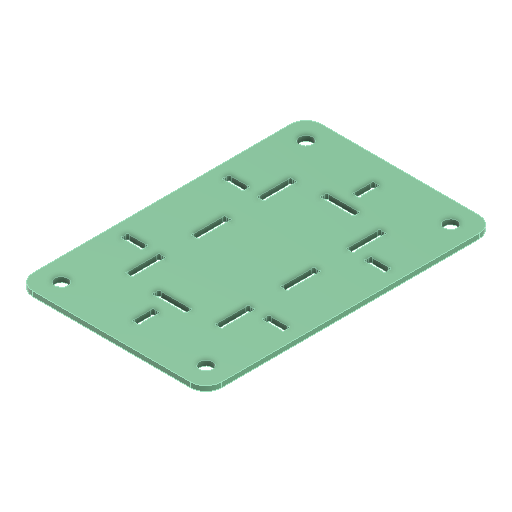
# Autodesk Inventor part: CUT_FR4_Waveguide_Back_Plate
Saved by Autodesk Inventor 2026.1 (Build 301233000, 233)
## iProperties
Created: 2025-11-04
Part Number: CUT_FR4_Waveguide_Back_Plate
Material: Generic
Document SubType Name: Modeling
Designer: User
Density: 1 g/cm^3
Appearance: Smooth - Dark Sea Green
Author: User
Autodesk Inventor part; units mm, degrees
ref_plane "YZ Plane" through (0, 0, 0) normal (1, 0, 0) x (0, 1, 0)
ref_plane "XZ Plane" through (0, 0, 0) normal (0, 1, 0) x (-1, 0, 0)
ref_plane "XY Plane" through (0, 0, 0) normal (0, 0, 1) x (1, 0, 0)
sketch "Sketch1" plane through (0, 0, 0) normal (0, 1, 0) x (-1, 0, 0)
  line L0 (14.0049, 35.6184) -> (-15.9951, 35.6184)
  line L1 (-15.9951, 35.6184) -> (-15.9951, -26.1816)
  line L2 (-15.9951, -26.1816) -> (14.0049, -26.1816)
  line L3 (14.0049, -26.1816) -> (14.0049, 35.6184)
  line L4 (29.0049, 50.6184) -> (-30.9951, 50.6184)
  line L5 (-30.9951, 50.6184) -> (-30.9951, -41.1816)
  line L6 (-30.9951, -41.1816) -> (29.0049, -41.1816)
  line L7 (29.0049, -41.1816) -> (29.0049, 50.6184)
  point P0 (0, 0)
  dimension "d0" = 30
  dimension "d1" = 61.8
  dimension "d4" = 15
  constraints: 16 end point, 4 parallel, 2 perpendicular, 1 horizontal, 3 other
  measures "d0" distance of L2.end L1.end
  measures "d1" distance of L1.end L0.end
  measures "d4" distance between parallel lines of L3 L7
extrude "Extrusion1" add sketch "Sketch1" along normal blind 1.6 contours L3 L2 L1 L0 | L7 L6 L5 L4
sketch "Sketch2" plane through (0, 1.6, 0) normal (0, 1, 0) x (1, 0, 0)
  line L0 (14.3951, 21.1816) -> (14.3951, 11.1816) construction
  line L1 (14.3951, 11.1816) -> (15.9951, 11.1816) construction
  line L2 (15.9951, 11.1816) -> (15.9951, 21.1816) construction
  line L3 (15.9951, 21.1816) -> (14.3951, 21.1816) construction
  line L4 (14.1451, 21.4316) -> (14.1451, 10.9316)
  line L5 (14.1451, 10.9316) -> (16.2451, 10.9316)
  line L6 (16.2451, 10.9316) -> (16.2451, 21.4316)
  line L7 (16.2451, 21.4316) -> (14.1451, 21.4316)
  line L8 (14.3951, 0.2816) -> (14.3951, -9.7184) construction
  line L9 (14.3951, -9.7184) -> (15.9951, -9.7184) construction
  line L10 (15.9951, -9.7184) -> (15.9951, 0.2816) construction
  line L11 (15.9951, 0.2816) -> (14.3951, 0.2816) construction
  line L12 (14.1451, 0.5316) -> (14.1451, -9.9684)
  line L13 (14.1451, -9.9684) -> (16.2451, -9.9684)
  line L14 (16.2451, -9.9684) -> (16.2451, 0.5316)
  line L15 (16.2451, 0.5316) -> (14.1451, 0.5316)
  line L16 (14.3951, -20.6184) -> (14.3951, -30.6184) construction
  line L17 (14.3951, -30.6184) -> (15.9951, -30.6184) construction
  line L18 (15.9951, -30.6184) -> (15.9951, -20.6184) construction
  line L19 (15.9951, -20.6184) -> (14.3951, -20.6184) construction
  line L20 (14.1451, -20.3684) -> (14.1451, -30.8684)
  line L21 (14.1451, -30.8684) -> (16.2451, -30.8684)
  line L22 (16.2451, -30.8684) -> (16.2451, -20.3684)
  line L23 (16.2451, -20.3684) -> (14.1451, -20.3684)
  dimension "d5" = 0.25
  dimension "d6" = 0.25
  dimension "d7" = 0.25
  constraints: 24 end point, 9 other
  measures "d5" distance between parallel lines of L4 L0
  measures "d6" distance between parallel lines of L12 L8
  measures "d7" distance between parallel lines of L20 L16
extrude "Extrusion2" cut sketch "Sketch2" against normal up to next
sketch "Sketch3" plane through (0, 1.6, 0) normal (0, 1, 0) x (1, 0, 0)
  circle A0 centre (15.8916, 0.178) radius 0.5
  circle A1 centre (15.8916, -9.6149) radius 0.5
  circle A2 centre (14.4987, -9.6149) radius 0.5
  circle A3 centre (14.4987, 0.178) radius 0.5
  circle A4 centre (15.8916, 21.078) radius 0.5
  circle A5 centre (15.8916, 11.2851) radius 0.5
  circle A6 centre (14.4987, 11.2851) radius 0.5
  circle A7 centre (14.4987, 21.078) radius 0.5
  circle A8 centre (15.8916, -20.722) radius 0.5
  circle A9 centre (15.8916, -30.5149) radius 0.5
  circle A10 centre (14.4987, -30.5149) radius 0.5
  circle A11 centre (14.4987, -20.722) radius 0.5
  point P0 (14.1451, 0.5316)
  point P1 (16.2451, -9.9684)
  point P2 (16.2451, 0.5316)
  point P3 (14.1451, -9.9684)
  point P4 (14.1451, 21.4316)
  point P5 (16.2451, 10.9316)
  point P6 (16.2451, 21.4316)
  point P7 (14.1451, 10.9316)
  point P8 (14.1451, -20.3684)
  point P9 (16.2451, -30.8684)
  point P10 (16.2451, -20.3684)
  point P11 (14.1451, -30.8684)
  dimension "d10" = 45
  dimension "d11" = 0.5
  dimension "d12" = 1
  dimension "d13" = 45
  dimension "d14" = 0.5
  dimension "d15" = 1
  dimension "d16" = 45
  dimension "d17" = 0.5
  dimension "d18" = 1
  dimension "d19" = 45
  dimension "d20" = 0.5
  dimension "d21" = 1
  dimension "d22" = 45
  dimension "d23" = 0.5
  dimension "d24" = 1
  dimension "d25" = 45
  dimension "d26" = 0.5
  dimension "d27" = 1
  dimension "d28" = 45
  dimension "d29" = 0.5
  dimension "d30" = 1
  dimension "d31" = 45
  dimension "d32" = 0.5
  dimension "d33" = 1
  dimension "d34" = 45
  dimension "d35" = 0.5
  dimension "d36" = 1
  dimension "d37" = 45
  dimension "d38" = 0.5
  dimension "d39" = 1
  dimension "d40" = 45
  dimension "d41" = 0.5
  dimension "d42" = 1
  dimension "d43" = 45
  dimension "d44" = 0.5
  dimension "d45" = 1
  constraints: 12 centre point
  measures "d11" distance of A0.centre point (16.245, 0.532)
  measures "d12" diameter of A0
  measures "d14" distance of A1.centre point (16.245, -9.968)
  measures "d15" diameter of A1
  measures "d17" distance of A2.centre point (14.145, -9.968)
  measures "d18" diameter of A2
  measures "d20" distance of A3.centre point (14.145, 0.532)
  measures "d21" diameter of A3
  measures "d23" distance of A4.centre point (16.245, 21.432)
  measures "d24" diameter of A4
  measures "d26" distance of A5.centre point (16.245, 10.932)
  measures "d27" diameter of A5
  measures "d29" distance of A6.centre point (14.145, 10.932)
  measures "d30" diameter of A6
  measures "d32" distance of A7.centre point (14.145, 21.432)
  measures "d33" diameter of A7
  measures "d35" distance of A8.centre point (16.245, -20.368)
  measures "d36" diameter of A8
  measures "d38" distance of A9.centre point (16.245, -30.868)
  measures "d39" diameter of A9
  measures "d41" distance of A10.centre point (14.145, -30.868)
  measures "d42" diameter of A10
  measures "d44" distance of A11.centre point (14.145, -20.368)
  measures "d45" diameter of A11
extrude "Extrusion3" cut sketch "Sketch3" against normal up to surface (1.6 mm away)
sketch "Sketch4" plane through (0, 1.6, 0) normal (0, 1, 0) x (1, 0, 0)
  line L0 (-12.4049, -30.6184) -> (-12.4049, -20.6184) construction
  line L1 (-12.4049, -20.6184) -> (-14.0049, -20.6184) construction
  line L2 (-14.0049, -20.6184) -> (-14.0049, -30.6184) construction
  line L3 (-14.0049, -30.6184) -> (-12.4049, -30.6184) construction
  line L4 (-12.1549, -30.8684) -> (-12.1549, -20.3684)
  line L5 (-12.1549, -20.3684) -> (-14.2549, -20.3684)
  line L6 (-14.2549, -20.3684) -> (-14.2549, -30.8684)
  line L7 (-14.2549, -30.8684) -> (-12.1549, -30.8684)
  line L8 (-12.4049, -9.7184) -> (-12.4049, 0.2816) construction
  line L9 (-12.4049, 0.2816) -> (-14.0049, 0.2816) construction
  line L10 (-14.0049, 0.2816) -> (-14.0049, -9.7184) construction
  line L11 (-14.0049, -9.7184) -> (-12.4049, -9.7184) construction
  line L12 (-12.1549, -9.9684) -> (-12.1549, 0.5316)
  line L13 (-12.1549, 0.5316) -> (-14.2549, 0.5316)
  line L14 (-14.2549, 0.5316) -> (-14.2549, -9.9684)
  line L15 (-14.2549, -9.9684) -> (-12.1549, -9.9684)
  line L16 (-12.4049, 11.1816) -> (-12.4049, 21.1816) construction
  line L17 (-12.4049, 21.1816) -> (-14.0049, 21.1816) construction
  line L18 (-14.0049, 21.1816) -> (-14.0049, 11.1816) construction
  line L19 (-14.0049, 11.1816) -> (-12.4049, 11.1816) construction
  line L20 (-12.1549, 10.9316) -> (-12.1549, 21.4316)
  line L21 (-12.1549, 21.4316) -> (-14.2549, 21.4316)
  line L22 (-14.2549, 21.4316) -> (-14.2549, 10.9316)
  line L23 (-14.2549, 10.9316) -> (-12.1549, 10.9316)
  dimension "d48" = 0.25
  dimension "d49" = 0.25
  dimension "d50" = 0.25
  constraints: 24 end point, 9 other
  measures "d48" distance between parallel lines of L4 L0
  measures "d49" distance between parallel lines of L12 L8
  measures "d50" distance between parallel lines of L20 L16
extrude "Extrusion4" cut sketch "Sketch4" against normal up to next
sketch "Sketch5" plane through (0, 1.6, 0) normal (0, 1, 0) x (1, 0, 0)
  circle A0 centre (-13.9013, -9.6149) radius 0.5
  circle A1 centre (-13.9013, 0.178) radius 0.5
  circle A2 centre (-12.5084, 0.178) radius 0.5
  circle A3 centre (-12.5084, -9.6149) radius 0.5
  circle A4 centre (-13.9013, -30.5149) radius 0.5
  circle A5 centre (-13.9013, -20.722) radius 0.5
  circle A6 centre (-12.5084, -20.722) radius 0.5
  circle A7 centre (-12.5084, -30.5149) radius 0.5
  circle A8 centre (-13.9013, 11.2851) radius 0.5
  circle A9 centre (-13.9013, 21.078) radius 0.5
  circle A10 centre (-12.5084, 21.078) radius 0.5
  circle A11 centre (-12.5084, 11.2851) radius 0.5
  point P0 (-12.1549, -9.9684)
  point P1 (-14.2549, 0.5316)
  point P2 (-14.2549, -9.9684)
  point P3 (-12.1549, 0.5316)
  point P4 (-12.1549, -30.8684)
  point P5 (-14.2549, -20.3684)
  point P6 (-14.2549, -30.8684)
  point P7 (-12.1549, -20.3684)
  point P8 (-12.1549, 10.9316)
  point P9 (-14.2549, 21.4316)
  point P10 (-14.2549, 10.9316)
  point P11 (-12.1549, 21.4316)
  dimension "d53" = 45
  dimension "d54" = 0.5
  dimension "d55" = 1
  dimension "d56" = 45
  dimension "d57" = 0.5
  dimension "d58" = 1
  dimension "d59" = 45
  dimension "d60" = 0.5
  dimension "d61" = 1
  dimension "d62" = 45
  dimension "d63" = 0.5
  dimension "d64" = 1
  dimension "d65" = 45
  dimension "d66" = 0.5
  dimension "d67" = 1
  dimension "d68" = 45
  dimension "d69" = 0.5
  dimension "d70" = 1
  dimension "d71" = 45
  dimension "d72" = 0.5
  dimension "d73" = 1
  dimension "d74" = 45
  dimension "d75" = 0.5
  dimension "d76" = 1
  dimension "d77" = 45
  dimension "d78" = 0.5
  dimension "d79" = 1
  dimension "d80" = 45
  dimension "d81" = 0.5
  dimension "d82" = 1
  dimension "d83" = 45
  dimension "d84" = 0.5
  dimension "d85" = 1
  dimension "d86" = 45
  dimension "d87" = 0.5
  dimension "d88" = 1
  constraints: 12 centre point
  measures "d54" distance of A0.centre point (-14.255, -9.968)
  measures "d55" diameter of A0
  measures "d57" distance of A1.centre point (-14.255, 0.532)
  measures "d58" diameter of A1
  measures "d60" distance of A2.centre point (-12.155, 0.532)
  measures "d61" diameter of A2
  measures "d63" distance of A3.centre point (-12.155, -9.968)
  measures "d64" diameter of A3
  measures "d66" distance of A4.centre point (-14.255, -30.868)
  measures "d67" diameter of A4
  measures "d69" distance of A5.centre point (-14.255, -20.368)
  measures "d70" diameter of A5
  measures "d72" distance of A6.centre point (-12.155, -20.368)
  measures "d73" diameter of A6
  measures "d75" distance of A7.centre point (-12.155, -30.868)
  measures "d76" diameter of A7
  measures "d78" distance of A8.centre point (-14.255, 10.932)
  measures "d79" diameter of A8
  measures "d81" distance of A9.centre point (-14.255, 21.432)
  measures "d82" diameter of A9
  measures "d84" distance of A10.centre point (-12.155, 21.432)
  measures "d85" diameter of A10
  measures "d87" distance of A11.centre point (-12.155, 10.932)
  measures "d88" diameter of A11
extrude "Extrusion5" cut sketch "Sketch5" against normal up to surface (1.6 mm away)
sketch "Sketch6" plane through (0, 1.6, 0) normal (0, 1, 0) x (1, 0, 0)
  line L0 (-4.0049, 21.1816) -> (5.9951, 21.1816) construction
  line L1 (5.9951, 21.1816) -> (5.9951, 22.7816) construction
  line L2 (5.9951, 22.7816) -> (-4.0049, 22.7816) construction
  line L3 (-4.0049, 22.7816) -> (-4.0049, 21.1816) construction
  line L4 (-4.2549, 20.9316) -> (6.2451, 20.9316)
  line L5 (6.2451, 20.9316) -> (6.2451, 23.0316)
  line L6 (6.2451, 23.0316) -> (-4.2549, 23.0316)
  line L7 (-4.2549, 23.0316) -> (-4.2549, 20.9316)
  dimension "d91" = 0.25
  constraints: 8 end point, 3 other
  measures "d91" distance between parallel lines of L4 L0
extrude "Extrusion6" cut sketch "Sketch6" against normal up to next
sketch "Sketch7" plane through (0, 1.6, 0) normal (0, 1, 0) x (1, 0, 0)
  circle A0 centre (-3.9013, 22.678) radius 0.5
  circle A1 centre (5.8916, 22.678) radius 0.5
  circle A2 centre (5.8916, 21.2851) radius 0.5
  circle A3 centre (-3.9013, 21.2851) radius 0.5
  point P0 (-4.2549, 20.9316)
  point P1 (6.2451, 23.0316)
  point P2 (-4.2549, 23.0316)
  point P3 (6.2451, 20.9316)
  dimension "d94" = 45
  dimension "d95" = 0.5
  dimension "d96" = 1
  dimension "d97" = 45
  dimension "d98" = 0.5
  dimension "d99" = 1
  dimension "d100" = 45
  dimension "d101" = 0.5
  dimension "d102" = 1
  dimension "d103" = 45
  dimension "d104" = 0.5
  dimension "d105" = 1
  constraints: 4 centre point
  measures "d95" distance of A0.centre point (-4.255, 23.032)
  measures "d96" diameter of A0
  measures "d98" distance of A1.centre point (6.245, 23.032)
  measures "d99" diameter of A1
  measures "d101" distance of A2.centre point (6.245, 20.932)
  measures "d102" diameter of A2
  measures "d104" distance of A3.centre point (-4.255, 20.932)
  measures "d105" diameter of A3
extrude "Extrusion7" cut sketch "Sketch7" against normal up to surface (1.6 mm away)
sketch "Sketch8" plane through (0, 1.6, 0) normal (0, 1, 0) x (1, 0, 0)
  line L0 (5.9951, -30.6184) -> (-4.0049, -30.6184) construction
  line L1 (-4.0049, -30.6184) -> (-4.0049, -32.2184) construction
  line L2 (-4.0049, -32.2184) -> (5.9951, -32.2184) construction
  line L3 (5.9951, -32.2184) -> (5.9951, -30.6184) construction
  line L4 (6.2451, -30.3684) -> (-4.2549, -30.3684)
  line L5 (-4.2549, -30.3684) -> (-4.2549, -32.4684)
  line L6 (-4.2549, -32.4684) -> (6.2451, -32.4684)
  line L7 (6.2451, -32.4684) -> (6.2451, -30.3684)
  dimension "d108" = 0.25
  constraints: 8 end point, 3 other
  measures "d108" distance between parallel lines of L4 L0
extrude "Extrusion8" cut sketch "Sketch8" against normal up to next
sketch "Sketch9" plane through (0, 1.6, 0) normal (0, 1, 0) x (1, 0, 0)
  circle A0 centre (5.8916, -32.1149) radius 0.5
  circle A1 centre (-3.9013, -32.1149) radius 0.5
  circle A2 centre (-3.9013, -30.722) radius 0.5
  circle A3 centre (5.8916, -30.722) radius 0.5
  point P0 (6.2451, -30.3684)
  point P1 (-4.2549, -32.4684)
  point P2 (6.2451, -32.4684)
  point P3 (-4.2549, -30.3684)
  dimension "d111" = 45
  dimension "d112" = 0.5
  dimension "d113" = 1
  dimension "d114" = 45
  dimension "d115" = 0.5
  dimension "d116" = 1
  dimension "d117" = 45
  dimension "d118" = 0.5
  dimension "d119" = 1
  dimension "d120" = 45
  dimension "d121" = 0.5
  dimension "d122" = 1
  constraints: 4 centre point
  measures "d112" distance of A0.centre point (6.245, -32.468)
  measures "d113" diameter of A0
  measures "d115" distance of A1.centre point (-4.255, -32.468)
  measures "d116" diameter of A1
  measures "d118" distance of A2.centre point (-4.255, -30.368)
  measures "d119" diameter of A2
  measures "d121" distance of A3.centre point (6.245, -30.368)
  measures "d122" diameter of A3
extrude "Extrusion9" cut sketch "Sketch9" against normal up to surface (1.6 mm away)
fillet "Fillet1" radius 5 4 edges at (30.9951, 0.8, 50.6184) (-29.0049, 0.8, 50.6184) (30.9951, 0.8, -41.1816) (-29.0049, 0.8, -41.1816)
sketch "Sketch10" plane through (0, 1.6, 0) normal (0, 1, 0) x (1, 0, 0)
  arc A0 (-24.0049, 41.1816) -> (-29.0049, 36.1816) centre (-24.0049, 36.1816) ccw projected
  line L0 (-29.0049, 36.1816) -> (-29.0049, -45.6184) projected
  arc A1 (-29.0049, -45.6184) -> (-24.0049, -50.6184) centre (-24.0049, -45.6184) ccw projected
  line L1 (-24.0049, -50.6184) -> (25.9951, -50.6184) projected
  arc A2 (25.9951, -50.6184) -> (30.9951, -45.6184) centre (25.9951, -45.6184) ccw projected
  line L2 (30.9951, -45.6184) -> (30.9951, 36.1816) projected
  arc A3 (30.9951, 36.1816) -> (25.9951, 41.1816) centre (25.9951, 36.1816) ccw projected
  line L3 (25.9951, 41.1816) -> (-24.0049, 41.1816) projected
  arc A4 (-3.5478, -30.3684) -> (-4.2549, -31.0756) centre (-3.9013, -30.722) ccw projected
  line L4 (-3.5478, -30.3684) -> (5.538, -30.3684) projected
  arc A5 (6.2451, -31.0756) -> (5.538, -30.3684) centre (5.8916, -30.722) ccw projected
  line L5 (6.2451, -31.0756) -> (6.2451, -31.7613) projected
  arc A6 (5.538, -32.4684) -> (6.2451, -31.7613) centre (5.8916, -32.1149) ccw projected
  line L6 (5.538, -32.4684) -> (-3.5478, -32.4684) projected
  arc A7 (-4.2549, -31.7613) -> (-3.5478, -32.4684) centre (-3.9013, -32.1149) ccw projected
  line L7 (-4.2549, -31.7613) -> (-4.2549, -31.0756) projected
  arc A8 (5.538, 20.9316) -> (6.2451, 21.6387) centre (5.8916, 21.2851) ccw projected
  line L8 (5.538, 20.9316) -> (-3.5478, 20.9316) projected
  arc A9 (-4.2549, 21.6387) -> (-3.5478, 20.9316) centre (-3.9013, 21.2851) ccw projected
  line L9 (-4.2549, 21.6387) -> (-4.2549, 22.3244) projected
  arc A10 (-3.5478, 23.0316) -> (-4.2549, 22.3244) centre (-3.9013, 22.678) ccw projected
  line L10 (-3.5478, 23.0316) -> (5.538, 23.0316) projected
  arc A11 (6.2451, 22.3244) -> (5.538, 23.0316) centre (5.8916, 22.678) ccw projected
  line L11 (6.2451, 22.3244) -> (6.2451, 21.6387) projected
  arc A12 (-12.1549, 20.7244) -> (-12.862, 21.4316) centre (-12.5084, 21.078) ccw projected
  line L12 (-12.1549, 20.7244) -> (-12.1549, 11.6387) projected
  arc A13 (-12.862, 10.9316) -> (-12.1549, 11.6387) centre (-12.5084, 11.2851) ccw projected
  line L13 (-12.862, 10.9316) -> (-13.5478, 10.9316) projected
  arc A14 (-14.2549, 11.6387) -> (-13.5478, 10.9316) centre (-13.9013, 11.2851) ccw projected
  line L14 (-14.2549, 11.6387) -> (-14.2549, 20.7244) projected
  arc A15 (-13.5478, 21.4316) -> (-14.2549, 20.7244) centre (-13.9013, 21.078) ccw projected
  line L15 (-13.5478, 21.4316) -> (-12.862, 21.4316) projected
  arc A16 (-12.862, -30.8684) -> (-12.1549, -30.1613) centre (-12.5084, -30.5149) ccw projected
  line L16 (-12.862, -30.8684) -> (-13.5478, -30.8684) projected
  arc A17 (-14.2549, -30.1613) -> (-13.5478, -30.8684) centre (-13.9013, -30.5149) ccw projected
  line L17 (-14.2549, -30.1613) -> (-14.2549, -21.0756) projected
  arc A18 (-13.5478, -20.3684) -> (-14.2549, -21.0756) centre (-13.9013, -20.722) ccw projected
  line L18 (-13.5478, -20.3684) -> (-12.862, -20.3684) projected
  arc A19 (-12.1549, -21.0756) -> (-12.862, -20.3684) centre (-12.5084, -20.722) ccw projected
  line L19 (-12.1549, -21.0756) -> (-12.1549, -30.1613) projected
  arc A20 (-12.862, -9.9684) -> (-12.1549, -9.2613) centre (-12.5084, -9.6149) ccw projected
  line L20 (-12.862, -9.9684) -> (-13.5478, -9.9684) projected
  arc A21 (-14.2549, -9.2613) -> (-13.5478, -9.9684) centre (-13.9013, -9.6149) ccw projected
  line L21 (-14.2549, -9.2613) -> (-14.2549, -0.1756) projected
  arc A22 (-13.5478, 0.5316) -> (-14.2549, -0.1756) centre (-13.9013, 0.178) ccw projected
  line L22 (-13.5478, 0.5316) -> (-12.862, 0.5316) projected
  arc A23 (-12.1549, -0.1756) -> (-12.862, 0.5316) centre (-12.5084, 0.178) ccw projected
  line L23 (-12.1549, -0.1756) -> (-12.1549, -9.2613) projected
  arc A24 (14.1451, -30.1613) -> (14.8522, -30.8684) centre (14.4987, -30.5149) ccw projected
  line L24 (14.1451, -30.1613) -> (14.1451, -21.0756) projected
  arc A25 (14.8522, -20.3684) -> (14.1451, -21.0756) centre (14.4987, -20.722) ccw projected
  line L25 (14.8522, -20.3684) -> (15.538, -20.3684) projected
  arc A26 (16.2451, -21.0756) -> (15.538, -20.3684) centre (15.8916, -20.722) ccw projected
  line L26 (16.2451, -21.0756) -> (16.2451, -30.1613) projected
  arc A27 (15.538, -30.8684) -> (16.2451, -30.1613) centre (15.8916, -30.5149) ccw projected
  line L27 (15.538, -30.8684) -> (14.8522, -30.8684) projected
  arc A28 (14.8522, 21.4316) -> (14.1451, 20.7244) centre (14.4987, 21.078) ccw projected
  line L28 (14.8522, 21.4316) -> (15.538, 21.4316) projected
  arc A29 (16.2451, 20.7244) -> (15.538, 21.4316) centre (15.8916, 21.078) ccw projected
  line L29 (16.2451, 20.7244) -> (16.2451, 11.6387) projected
  arc A30 (15.538, 10.9316) -> (16.2451, 11.6387) centre (15.8916, 11.2851) ccw projected
  line L30 (15.538, 10.9316) -> (14.8522, 10.9316) projected
  arc A31 (14.1451, 11.6387) -> (14.8522, 10.9316) centre (14.4987, 11.2851) ccw projected
  line L31 (14.1451, 11.6387) -> (14.1451, 20.7244) projected
  arc A32 (14.8522, 0.5316) -> (14.1451, -0.1756) centre (14.4987, 0.178) ccw projected
  line L32 (14.8522, 0.5316) -> (15.538, 0.5316) projected
  arc A33 (16.2451, -0.1756) -> (15.538, 0.5316) centre (15.8916, 0.178) ccw projected
  line L33 (16.2451, -0.1756) -> (16.2451, -9.2613) projected
  arc A34 (15.538, -9.9684) -> (16.2451, -9.2613) centre (15.8916, -9.6149) ccw projected
  line L34 (15.538, -9.9684) -> (14.8522, -9.9684) projected
  arc A35 (14.1451, -9.2613) -> (14.8522, -9.9684) centre (14.4987, -9.6149) ccw projected
  line L35 (14.1451, -9.2613) -> (14.1451, -0.1756) projected
  point P0 (0, 0)
  point P1 (-22.0049, -43.6184)
  point P2 (-22.0049, 34.1816)
  point P3 (23.9951, 34.1816)
  point P4 (23.9951, -43.6184)
  dimension "d126" = 7
  dimension "d127" = 7
  dimension "d128" = 7
  dimension "d129" = 7
  constraints: 2 horizontal alignment, 2 vertical alignment
  measures "d126" distance from line of L1 point (-22.005, -43.618)
  measures "d127" distance from line of L0 point (-22.005, -43.618)
  measures "d128" distance from line of L3 point (-22.005, 34.182)
  measures "d129" distance from line of L2 point (23.995, -43.618)
hole "Hole1" at (-22.0049, 1.6, 43.6184) at (-22.0049, 1.6, -34.1816) at (23.9951, 1.6, -34.1816) at (23.9951, 1.6, 43.6184) direction (0, -1, 0) diameter 4.2 end through all
sketch "Sketch11" plane through (0, 1.6, 0) normal (0, 1, 0) x (1, 0, 0)
  line L0 (-24.5049, -21.6684) -> (-18.5049, -21.6684) construction
  line L1 (-18.5049, -21.6684) -> (-18.5049, -20.0684) construction
  line L2 (-18.5049, -20.0684) -> (-24.5049, -20.0684) construction
  line L3 (-24.5049, -20.0684) -> (-24.5049, -21.6684) construction
  line L4 (-24.7549, -21.9184) -> (-18.2549, -21.9184)
  line L5 (-18.2549, -21.9184) -> (-18.2549, -19.8184)
  line L6 (-18.2549, -19.8184) -> (-24.7549, -19.8184)
  line L7 (-24.7549, -19.8184) -> (-24.7549, -21.9184)
  dimension "d137" = 0.25
  constraints: 8 end point, 3 other
  measures "d137" distance between parallel lines of L4 L0
extrude "Extrusion10" cut sketch "Sketch11" against normal up to next
sketch "Sketch12" plane through (0, 1.6, 0) normal (0, 1, 0) x (1, 0, 0)
  circle A0 centre (-24.4013, -20.172) radius 0.5
  circle A1 centre (-18.6084, -20.172) radius 0.5
  circle A2 centre (-18.6084, -21.5649) radius 0.5
  circle A3 centre (-24.4013, -21.5649) radius 0.5
  point P0 (-24.7549, -21.9184)
  point P1 (-18.2549, -19.8184)
  point P2 (-24.7549, -19.8184)
  point P3 (-18.2549, -21.9184)
  dimension "d140" = 45
  dimension "d141" = 0.5
  dimension "d142" = 1
  dimension "d143" = 45
  dimension "d144" = 0.5
  dimension "d145" = 1
  dimension "d146" = 45
  dimension "d147" = 0.5
  dimension "d148" = 1
  dimension "d149" = 45
  dimension "d150" = 0.5
  dimension "d151" = 1
  constraints: 4 centre point
  measures "d141" distance of A0.centre point (-24.755, -19.818)
  measures "d142" diameter of A0
  measures "d144" distance of A1.centre point (-18.255, -19.818)
  measures "d145" diameter of A1
  measures "d147" distance of A2.centre point (-18.255, -21.918)
  measures "d148" diameter of A2
  measures "d150" distance of A3.centre point (-24.755, -21.918)
  measures "d151" diameter of A3
extrude "Extrusion11" cut sketch "Sketch12" against normal up to surface (1.6 mm away)
sketch "Sketch13" plane through (0, 1.6, 0) normal (0, 1, 0) x (1, 0, 0)
  line L0 (-24.5049, 10.6316) -> (-18.5049, 10.6316) construction
  line L1 (-18.5049, 10.6316) -> (-18.5049, 12.2316) construction
  line L2 (-18.5049, 12.2316) -> (-24.5049, 12.2316) construction
  line L3 (-24.5049, 12.2316) -> (-24.5049, 10.6316) construction
  line L4 (-24.7549, 10.3816) -> (-18.2549, 10.3816)
  line L5 (-18.2549, 10.3816) -> (-18.2549, 12.4816)
  line L6 (-18.2549, 12.4816) -> (-24.7549, 12.4816)
  line L7 (-24.7549, 12.4816) -> (-24.7549, 10.3816)
  dimension "d154" = 0.25
  constraints: 8 end point, 3 other
  measures "d154" distance between parallel lines of L4 L0
extrude "Extrusion12" cut sketch "Sketch13" against normal up to next
sketch "Sketch14" plane through (0, 1.6, 0) normal (0, 1, 0) x (1, 0, 0)
  circle A0 centre (-24.4013, 12.128) radius 0.5
  circle A1 centre (-18.6084, 12.128) radius 0.5
  circle A2 centre (-18.6084, 10.7351) radius 0.5
  circle A3 centre (-24.4013, 10.7351) radius 0.5
  point P0 (-24.7549, 10.3816)
  point P1 (-18.2549, 12.4816)
  point P2 (-24.7549, 12.4816)
  point P3 (-18.2549, 10.3816)
  dimension "d157" = 45
  dimension "d158" = 0.5
  dimension "d159" = 1
  dimension "d160" = 45
  dimension "d161" = 0.5
  dimension "d162" = 1
  dimension "d163" = 45
  dimension "d164" = 0.5
  dimension "d165" = 1
  dimension "d166" = 45
  dimension "d167" = 0.5
  dimension "d168" = 1
  constraints: 4 centre point
  measures "d158" distance of A0.centre point (-24.755, 12.482)
  measures "d159" diameter of A0
  measures "d161" distance of A1.centre point (-18.255, 12.482)
  measures "d162" diameter of A1
  measures "d164" distance of A2.centre point (-18.255, 10.382)
  measures "d165" diameter of A2
  measures "d167" distance of A3.centre point (-24.755, 10.382)
  measures "d168" diameter of A3
extrude "Extrusion13" cut sketch "Sketch14" against normal up to surface (1.6 mm away)
sketch "Sketch15" plane through (0, 1.6, 0) normal (0, 1, 0) x (1, 0, 0)
  line L0 (26.4951, 12.2316) -> (20.4951, 12.2316) construction
  line L1 (20.4951, 12.2316) -> (20.4951, 10.6316) construction
  line L2 (20.4951, 10.6316) -> (26.4951, 10.6316) construction
  line L3 (26.4951, 10.6316) -> (26.4951, 12.2316) construction
  line L4 (26.7451, 12.4816) -> (20.2451, 12.4816)
  line L5 (20.2451, 12.4816) -> (20.2451, 10.3816)
  line L6 (20.2451, 10.3816) -> (26.7451, 10.3816)
  line L7 (26.7451, 10.3816) -> (26.7451, 12.4816)
  dimension "d171" = 0.25
  constraints: 8 end point, 3 other
  measures "d171" distance between parallel lines of L4 L0
extrude "Extrusion14" cut sketch "Sketch15" against normal up to next
sketch "Sketch16" plane through (0, 1.6, 0) normal (0, 1, 0) x (1, 0, 0)
  circle A0 centre (26.3916, 10.7351) radius 0.5
  circle A1 centre (20.5987, 10.7351) radius 0.5
  circle A2 centre (20.5987, 12.128) radius 0.5
  circle A3 centre (26.3916, 12.128) radius 0.5
  point P0 (26.7451, 12.4816)
  point P1 (20.2451, 10.3816)
  point P2 (26.7451, 10.3816)
  point P3 (20.2451, 12.4816)
  dimension "d174" = 45
  dimension "d175" = 0.5
  dimension "d176" = 1
  dimension "d177" = 45
  dimension "d178" = 0.5
  dimension "d179" = 1
  dimension "d180" = 45
  dimension "d181" = 0.5
  dimension "d182" = 1
  dimension "d183" = 45
  dimension "d184" = 0.5
  dimension "d185" = 1
  constraints: 4 centre point
  measures "d175" distance of A0.centre point (26.745, 10.382)
  measures "d176" diameter of A0
  measures "d178" distance of A1.centre point (20.245, 10.382)
  measures "d179" diameter of A1
  measures "d181" distance of A2.centre point (20.245, 12.482)
  measures "d182" diameter of A2
  measures "d184" distance of A3.centre point (26.745, 12.482)
  measures "d185" diameter of A3
extrude "Extrusion15" cut sketch "Sketch16" against normal up to surface (1.6 mm away)
sketch "Sketch17" plane through (0, 1.6, 0) normal (0, 1, 0) x (1, 0, 0)
  line L0 (26.4951, -20.0684) -> (20.4951, -20.0684) construction
  line L1 (20.4951, -20.0684) -> (20.4951, -21.6684) construction
  line L2 (20.4951, -21.6684) -> (26.4951, -21.6684) construction
  line L3 (26.4951, -21.6684) -> (26.4951, -20.0684) construction
  line L4 (26.7451, -19.8184) -> (20.2451, -19.8184)
  line L5 (20.2451, -19.8184) -> (20.2451, -21.9184)
  line L6 (20.2451, -21.9184) -> (26.7451, -21.9184)
  line L7 (26.7451, -21.9184) -> (26.7451, -19.8184)
  dimension "d188" = 0.25
  constraints: 8 end point, 3 other
  measures "d188" distance between parallel lines of L4 L0
extrude "Extrusion16" cut sketch "Sketch17" against normal up to next
sketch "Sketch18" plane through (0, 1.6, 0) normal (0, 1, 0) x (1, 0, 0)
  circle A0 centre (26.3916, -21.5649) radius 0.5
  circle A1 centre (20.5987, -21.5649) radius 0.5
  circle A2 centre (20.5987, -20.172) radius 0.5
  circle A3 centre (26.3916, -20.172) radius 0.5
  point P0 (26.7451, -19.8184)
  point P1 (20.2451, -21.9184)
  point P2 (26.7451, -21.9184)
  point P3 (20.2451, -19.8184)
  dimension "d191" = 45
  dimension "d192" = 0.5
  dimension "d193" = 1
  dimension "d194" = 45
  dimension "d195" = 0.5
  dimension "d196" = 1
  dimension "d197" = 45
  dimension "d198" = 0.5
  dimension "d199" = 1
  dimension "d200" = 45
  dimension "d201" = 0.5
  dimension "d202" = 1
  constraints: 4 centre point
  measures "d192" distance of A0.centre point (26.745, -21.918)
  measures "d193" diameter of A0
  measures "d195" distance of A1.centre point (20.245, -21.918)
  measures "d196" diameter of A1
  measures "d198" distance of A2.centre point (20.245, -19.818)
  measures "d199" diameter of A2
  measures "d201" distance of A3.centre point (26.745, -19.818)
  measures "d202" diameter of A3
extrude "Extrusion17" cut sketch "Sketch18" against normal up to surface (1.6 mm away)
sketch "Sketch19" plane through (0, 1.6, 0) normal (0, 1, 0) x (1, 0, 0)
  line L0 (0.1951, 33.2816) -> (0.1951, 27.2816) construction
  line L1 (0.1951, 27.2816) -> (1.7951, 27.2816) construction
  line L2 (1.7951, 27.2816) -> (1.7951, 33.2816) construction
  line L3 (1.7951, 33.2816) -> (0.1951, 33.2816) construction
  line L4 (-0.0549, 33.5316) -> (-0.0549, 27.0316)
  line L5 (-0.0549, 27.0316) -> (2.0451, 27.0316)
  line L6 (2.0451, 27.0316) -> (2.0451, 33.5316)
  line L7 (2.0451, 33.5316) -> (-0.0549, 33.5316)
  dimension "d205" = 0.25
  constraints: 8 end point, 3 other
  measures "d205" distance between parallel lines of L4 L0
extrude "Extrusion18" cut sketch "Sketch19" against normal up to next
sketch "Sketch20" plane through (0, 1.6, 0) normal (0, 1, 0) x (1, 0, 0)
  circle A0 centre (1.6916, 33.178) radius 0.5
  circle A1 centre (1.6916, 27.3851) radius 0.5
  circle A2 centre (0.2987, 27.3851) radius 0.5
  circle A3 centre (0.2987, 33.178) radius 0.5
  point P0 (-0.0549, 33.5316)
  point P1 (2.0451, 27.0316)
  point P2 (2.0451, 33.5316)
  point P3 (-0.0549, 27.0316)
  dimension "d208" = 45
  dimension "d209" = 0.5
  dimension "d210" = 1
  dimension "d211" = 45
  dimension "d212" = 0.5
  dimension "d213" = 1
  dimension "d214" = 45
  dimension "d215" = 0.5
  dimension "d216" = 1
  dimension "d217" = 45
  dimension "d218" = 0.5
  dimension "d219" = 1
  constraints: 4 centre point
  measures "d209" distance of A0.centre point (2.045, 33.532)
  measures "d210" diameter of A0
  measures "d212" distance of A1.centre point (2.045, 27.032)
  measures "d213" diameter of A1
  measures "d215" distance of A2.centre point (-0.055, 27.032)
  measures "d216" diameter of A2
  measures "d218" distance of A3.centre point (-0.055, 33.532)
  measures "d219" diameter of A3
extrude "Extrusion19" cut sketch "Sketch20" against normal up to surface (1.6 mm away)
sketch "Sketch21" plane through (0, 1.6, 0) normal (0, 1, 0) x (1, 0, 0)
  line L0 (1.7951, -42.7184) -> (1.7951, -36.7184) construction
  line L1 (1.7951, -36.7184) -> (0.1951, -36.7184) construction
  line L2 (0.1951, -36.7184) -> (0.1951, -42.7184) construction
  line L3 (0.1951, -42.7184) -> (1.7951, -42.7184) construction
  line L4 (2.0451, -42.9684) -> (2.0451, -36.4684)
  line L5 (2.0451, -36.4684) -> (-0.0549, -36.4684)
  line L6 (-0.0549, -36.4684) -> (-0.0549, -42.9684)
  line L7 (-0.0549, -42.9684) -> (2.0451, -42.9684)
  dimension "d222" = 0.25
  constraints: 8 end point, 3 other
  measures "d222" distance between parallel lines of L4 L0
extrude "Extrusion20" cut sketch "Sketch21" against normal up to next
sketch "Sketch22" plane through (0, 1.6, 0) normal (0, 1, 0) x (1, 0, 0)
  circle A0 centre (0.2987, -42.6149) radius 0.5
  circle A1 centre (0.2987, -36.822) radius 0.5
  circle A2 centre (1.6916, -36.822) radius 0.5
  circle A3 centre (1.6916, -42.6149) radius 0.5
  point P0 (2.0451, -42.9684)
  point P1 (-0.0549, -36.4684)
  point P2 (-0.0549, -42.9684)
  point P3 (2.0451, -36.4684)
  dimension "d225" = 45
  dimension "d226" = 0.5
  dimension "d227" = 1
  dimension "d228" = 45
  dimension "d229" = 0.5
  dimension "d230" = 1
  dimension "d231" = 45
  dimension "d232" = 0.5
  dimension "d233" = 1
  dimension "d234" = 45
  dimension "d235" = 0.5
  dimension "d236" = 1
  constraints: 4 centre point
  measures "d226" distance of A0.centre point (-0.055, -42.968)
  measures "d227" diameter of A0
  measures "d229" distance of A1.centre point (-0.055, -36.468)
  measures "d230" diameter of A1
  measures "d232" distance of A2.centre point (2.045, -36.468)
  measures "d233" diameter of A2
  measures "d235" distance of A3.centre point (2.045, -42.968)
  measures "d236" diameter of A3
extrude "Extrusion21" cut sketch "Sketch22" against normal up to surface (1.6 mm away)
equation "\"d127\" = d126"
equation "\"d128\" = d126"
equation "\"d129\" = d126"
body "Solid1"
